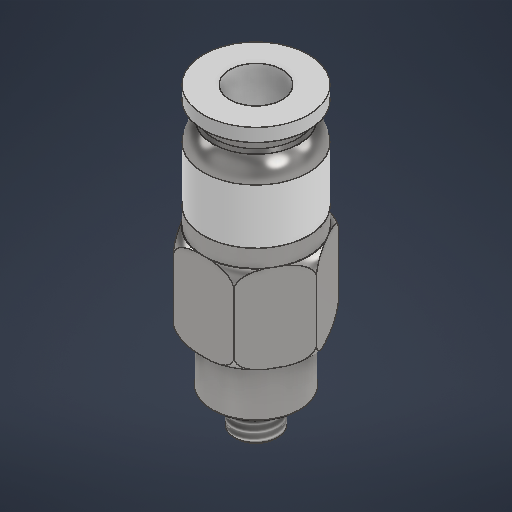
# Autodesk Inventor part: VPC6-M5
Saved by Autodesk Inventor 2026.2 (Build 302298010, 298A)
## iProperties
Created: 2026-05-07
Part Number: VPC6-M5
Material: 스테인리스스틸
Document SubType Name: Modeling
Designer: work
Density: 8 g/cm^3
Appearance: 반연마
Author: work
Autodesk Inventor part; units mm, degrees
ref_plane "YZ Plane" through (0, 0, 0) normal (1, 0, 0) x (0, 1, 0)
ref_plane "XZ Plane" through (0, 0, 0) normal (0, 1, 0) x (-1, 0, 0)
sketch "스케치1" plane through (0, 0, 0) normal (0, 1, 0) x (-1, 0, 0)
  circle A0 centre (0, 0) radius 5
  dimension "d0" = 10
  constraints: 1 centre point, 1 coincident
  measures "d0" diameter of A0
extrude "돌출1" add sketch "스케치1" along normal blind 6
sketch "스케치2" plane through (0, 0, 0) normal (0, -1, 0) x (1, 0, 0)
  circle A0 centre (0, 0) radius 2.5
  dimension "d3" = 5
  constraints: 1 centre point, 1 coincident
  measures "d3" diameter of A0
extrude "돌출2" add sketch "스케치2" along normal blind 4
thread "스레드1" size "M5x0.8" class "6g" standard "ISO Metric profile" full length
sketch "스케치3" plane through (0, 6, 0) normal (0, 1, 0) x (1, 0, 0)
  line L0 (-3.4641, -6) -> (-6.9282, 0)
  line L1 (-6.9282, 0) -> (-3.4641, 6)
  line L2 (-3.4641, 6) -> (3.4641, 6)
  line L3 (3.4641, 6) -> (6.9282, 0)
  line L4 (6.9282, 0) -> (3.4641, -6)
  line L5 (3.4641, -6) -> (-3.4641, -6)
  line L6 (0, 0) -> (0, -6) construction
  dimension "d8" = 12
  constraints: 14 end point, 1 coincident, 1 midpoint, 1 vertical, 13 other
  measures "d8" distance between parallel lines of L2 L5
extrude "돌출3" add sketch "스케치3" along normal blind 10
sketch "스케치4" plane through (0, 16, 0) normal (0, 1, 0) x (1, 0, 0)
  circle A0 centre (0, 0) radius 6
  dimension "d11" = 12
  constraints: 1 centre point, 1 coincident
  measures "d11" diameter of A0
extrude "돌출4" add sketch "스케치4" along normal blind 8
sketch "스케치5" plane through (0, 0, 0) normal (0, 0, 1) x (1, 0, 0)
  line L0 (6, 24) -> (-6, 24) projected
  arc A0 (-4.75, 26.75) -> (-6, 24) centre (-2.35, 24) ccw
  line L1 (-4.75, 26.75) -> (0, 26.75) construction
  line L2 (0, 26.75) -> (0, 24) construction
  line L3 (-4.75, 26.75) -> (-4.75, 27.75)
  line L4 (-4.75, 27.75) -> (-3.5, 27.75)
  line L5 (-3.5, 27.75) -> (-3.5, 28.5)
  line L6 (-3.5, 28.5) -> (-6, 28.5)
  line L7 (-6, 28.5) -> (-6, 30)
  line L8 (-6, 30) -> (0, 30)
  line L9 (0, 30) -> (0, 24)
  line L10 (5, 0) -> (-5, 0) projected
  line L11 (-6, 16) -> (-6, 24) projected
  point P0 (0, 0)
  point P1 (-6, 29.25)
  point P2 (-3.5, 28.125)
  dimension "d14" = 30
  dimension "d15" = 12
  dimension "d16" = 1.5
  dimension "d17" = 9.5
  dimension "d18" = 7
  dimension "d19" = 1
  dimension "d20" = 0.75
  constraints: 18 end point, 4 perpendicular, 3 midpoint, 2 point on circle, 2 vertical, 1 centre point, 1 horizontal, 1 parallel, 1 point on line, 1 tangent
  measures "d14" distance between parallel lines of L10 L8
  measures "d15" diameter of point (-6, 29.25) L9
  measures "d16" distance between parallel lines of L6 L8
  measures "d17" diameter of L3 L9
  measures "d18" diameter of point (-3.5, 28.125) L9
  measures "d19" distance of L1.start L3.end
  measures "d20" distance of L4.end L5.end
revolve "회전1" add sketch "스케치5" angle 360 about axis through (0, 30, 0) along (0, -1, 0)
sketch "스케치6" plane through (0, 30, 0) normal (0, 1, 0) x (1, 0, 0)
  circle A0 centre (0, 0) radius 2.5 projected
  circle A1 centre (0, 0) radius 3
  dimension "d22" = 6
  constraints: 1 centre point, 1 coincident
  measures "d22" diameter of A1
extrude "돌출5" cut sketch "스케치6" against normal blind 8 contours A0 | A1
ref_plane "작업 평면1" through (0, 18, 0) normal (0, 1, 0) x (1, 0, 0)
sketch "스케치7" plane through (0, 18, 0) normal (0, 1, 0) x (1, 0, 0)
  circle A0 centre (0, 0) radius 5.99
  arc A1 (5.1962, 3) -> (0, 6) centre (0, 0) ccw projected
  circle A2 centre (0, 0) radius 6
  point P0 (0, 6)
  dimension "d26" = 0.01
  constraints: 2 coincident, 1 centre point, 1 concentric, 3 other
  measures "d26" radial gap between concentric circles of A1 A0
extrude "돌출6" cut sketch "스케치7" along normal blind 7
chamfer "모따기1" distance 0.25 angle 45 4 edges at (-2.5, -4, 0) (5, 0, 0) (5, 6, 0) (4.75, 26.75, 0)
sketch "스케치8" plane through (0, 0, 0) normal (0, 0, 1) x (1, 0, 0)
  line L0 (6.9282, 16) -> (5.1962, 16) projected
  line L1 (6.9282, 6) -> (3.4641, 6) projected
  line L2 (3.4641, 6) -> (3.4641, 16) projected
  line L3 (5.1962, 16) -> (3.4641, 16) projected
  line L4 (6.9282, 16) -> (5.1962, 16) projected
  line L5 (6.9282, 6) -> (6.9282, 16) projected
  arc A0 (6.9282, 14.3525) -> (6.0622, 16) centre (4.9282, 14.3525) ccw
  line L6 (6.9282, 11) -> (0, 11) construction
  arc A1 (6.0622, 6) -> (6.9282, 7.6475) centre (4.9282, 7.6475) ccw
  line L7 (0, 16) -> (0, 5.3892)
  point P0 (0, 0)
  point P1 (6.9282, 7.6475)
  point P2 (6.0622, 6)
  dimension "d32" = 2
  constraints: 4 end point, 4 point on circle, 3 symmetric about line, 2 centre point, 2 midpoint, 1 horizontal, 1 parallel, 1 point on line, 1 tangent, 1 vertical, 1 other
  measures "d32" radius of A0
revolve "회전2" cut sketch "스케치8" angle 360 about axis through (0, 16, 0) along (0, -1, 0) contours L5 A0 L0 | L5 L1 A1
